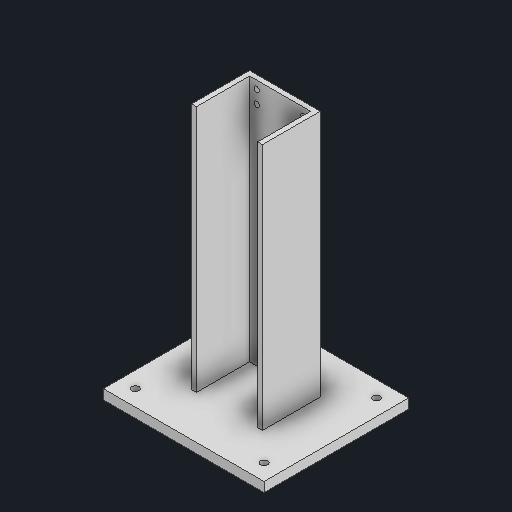
# Autodesk Inventor part: 01_Base
Saved by Autodesk Inventor 2027.2 (Build 312334000, 334)
## iProperties
Created: 2026-11-14
Part Number: 01_Base
Material: Genérico
Document SubType Name: Modeling
Designer: alexa
Density: 1 g/cm^3
Appearance: Valor por defecto
Mass: 104.329 g
Surface Area: 553.516 cm^2
Volume: 104.329 cm^3
Author: alexa
Autodesk Inventor part; units mm, degrees
ref_plane "Pie_100x90x6_perfil_plano" through (0, 0, -45) normal (0, 0, 1) x (1, 0, 0)
sketch "Pie_100x90x6_perfil" plane through (0, 0, -45) normal (0, 0, 1) x (1, 0, 0)
  line L0 (-55.5, 0) -> (44.5, 0)
  line L1 (44.5, 0) -> (44.5, 6)
  line L2 (44.5, 6) -> (-55.5, 6)
  line L3 (-55.5, 6) -> (-55.5, 0)
  constraints: 8 end point, 2 parallel, 1 horizontal, 1 perpendicular
extrude "Pie_100x90x6" add sketch "Pie_100x90x6_perfil" along normal blind 90
ref_plane "Pared_izquierda_perfil_plano" through (0, 0, -18) normal (0, 0, 1) x (1, 0, 0)
sketch "Pared_izquierda_perfil" plane through (0, 0, -18) normal (0, 0, 1) x (1, 0, 0)
  line L0 (-27.5, 6) -> (-24.5, 6)
  line L1 (-24.5, 6) -> (-24.5, 160)
  line L2 (-24.5, 160) -> (-27.5, 160)
  line L3 (-27.5, 160) -> (-27.5, 6)
  constraints: 8 end point, 2 parallel, 1 horizontal, 1 perpendicular
extrude "Pared_izquierda" add sketch "Pared_izquierda_perfil" along normal blind 36
ref_plane "Pared_derecha_perfil_plano" through (0, 0, -18) normal (0, 0, 1) x (1, 0, 0)
sketch "Pared_derecha_perfil" plane through (0, 0, -18) normal (0, 0, 1) x (1, 0, 0)
  line L0 (13.5, 6) -> (16.5, 6)
  line L1 (16.5, 6) -> (16.5, 160)
  line L2 (16.5, 160) -> (13.5, 160)
  line L3 (13.5, 160) -> (13.5, 6)
  constraints: 8 end point, 2 parallel, 1 horizontal, 1 perpendicular
extrude "Pared_derecha" add sketch "Pared_derecha_perfil" along normal blind 36
ref_plane "Cara_frontal_perfil_plano" through (0, 0, -18) normal (0, 0, 1) x (1, 0, 0)
sketch "Cara_frontal_perfil" plane through (0, 0, -18) normal (0, 0, 1) x (1, 0, 0)
  line L0 (-24.5, 6) -> (13.5, 6)
  line L1 (13.5, 6) -> (13.5, 160)
  line L2 (13.5, 160) -> (-24.5, 160)
  line L3 (-24.5, 160) -> (-24.5, 6)
  constraints: 8 end point, 2 parallel, 1 horizontal, 1 perpendicular
extrude "Cara_frontal" add sketch "Cara_frontal_perfil" along normal blind 3
ref_plane "Anclaje_-45.5_-35_perfil_plano" through (0, -0.1, 0) normal (0, 1, 0) x (-1, 0, 0)
sketch "Anclaje_-45.5_-35_perfil" plane through (0, -0.1, 0) normal (0, 1, 0) x (-1, 0, 0)
  circle A0 centre (45.5, -35) radius 2.25
  constraints: 1 centre point
extrude "Anclaje_-45.5_-35" cut sketch "Anclaje_-45.5_-35_perfil" along normal blind 6.2
ref_plane "Anclaje_-45.5_35_perfil_plano" through (0, -0.1, 0) normal (0, 1, 0) x (-1, 0, 0)
sketch "Anclaje_-45.5_35_perfil" plane through (0, -0.1, 0) normal (0, 1, 0) x (-1, 0, 0)
  circle A0 centre (45.5, 35) radius 2.25
  constraints: 1 centre point
extrude "Anclaje_-45.5_35" cut sketch "Anclaje_-45.5_35_perfil" along normal blind 6.2
ref_plane "Anclaje_34.5_-35_perfil_plano" through (0, -0.1, 0) normal (0, 1, 0) x (-1, 0, 0)
sketch "Anclaje_34.5_-35_perfil" plane through (0, -0.1, 0) normal (0, 1, 0) x (-1, 0, 0)
  circle A0 centre (-34.5, -35) radius 2.25
  constraints: 1 centre point
extrude "Anclaje_34.5_-35" cut sketch "Anclaje_34.5_-35_perfil" along normal blind 6.2
ref_plane "Anclaje_34.5_35_perfil_plano" through (0, -0.1, 0) normal (0, 1, 0) x (-1, 0, 0)
sketch "Anclaje_34.5_35_perfil" plane through (0, -0.1, 0) normal (0, 1, 0) x (-1, 0, 0)
  circle A0 centre (-34.5, 35) radius 2.25
  constraints: 1 centre point
extrude "Anclaje_34.5_35" cut sketch "Anclaje_34.5_35_perfil" along normal blind 6.2
ref_plane "Union_-20_147_perfil_plano" through (0, 0, -18.1) normal (0, 0, 1) x (1, 0, 0)
sketch "Union_-20_147_perfil" plane through (0, 0, -18.1) normal (0, 0, 1) x (1, 0, 0)
  circle A0 centre (-20, 147) radius 1.7
  constraints: 1 centre point
extrude "Union_-20_147" cut sketch "Union_-20_147_perfil" along normal blind 3.2
ref_plane "Union_-20_155_perfil_plano" through (0, 0, -18.1) normal (0, 0, 1) x (1, 0, 0)
sketch "Union_-20_155_perfil" plane through (0, 0, -18.1) normal (0, 0, 1) x (1, 0, 0)
  circle A0 centre (-20, 155) radius 1.7
  constraints: 1 centre point
extrude "Union_-20_155" cut sketch "Union_-20_155_perfil" along normal blind 3.2
ref_plane "Union_9_147_perfil_plano" through (0, 0, -18.1) normal (0, 0, 1) x (1, 0, 0)
sketch "Union_9_147_perfil" plane through (0, 0, -18.1) normal (0, 0, 1) x (1, 0, 0)
  circle A0 centre (9, 147) radius 1.7
  constraints: 1 centre point
extrude "Union_9_147" cut sketch "Union_9_147_perfil" along normal blind 3.2
ref_plane "Union_9_155_perfil_plano" through (0, 0, -18.1) normal (0, 0, 1) x (1, 0, 0)
sketch "Union_9_155_perfil" plane through (0, 0, -18.1) normal (0, 0, 1) x (1, 0, 0)
  circle A0 centre (9, 155) radius 1.7
  constraints: 1 centre point
extrude "Union_9_155" cut sketch "Union_9_155_perfil" along normal blind 3.2
